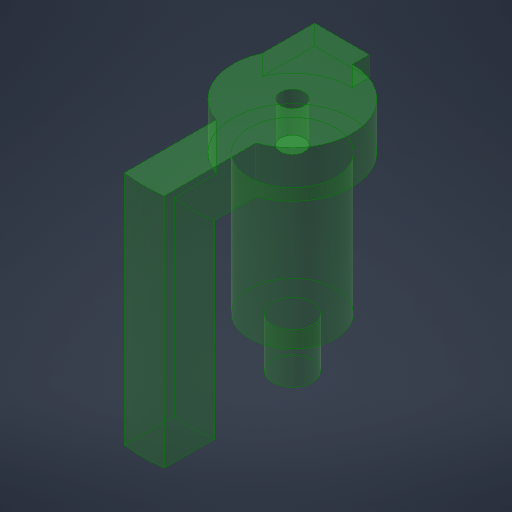
# Autodesk Inventor part: OT2-Pipette V0.4 - yoke
Saved by Autodesk Inventor 2026 (Build 300175000, 175)
## iProperties
Created: 2026-11-01
Part Number: OT2-Pipette V0.4 - yoke
Material: Generisch
Description: printed yoke on the actuator shaft (M2.5 insert), rigid pad on the plunger knob, switch tab
Document SubType Name: Modeling
Designer: benir
Density: 1 g/cm^3
Appearance: Green
Author: benir
Autodesk Inventor part; units mm, degrees
ref_plane "y=top_y - disc_h" through (0, 95, 0) normal (0, 1, 0) x (-1, 0, 0)
sketch "disc" plane through (0, 95, 0) normal (0, 1, 0) x (-1, 0, 0)
  circle A0 centre (-8.2, -3.46) radius 9
  point P0 (0, 0)
  dimension "d3" = 3.46
  dimension "d4" = 8.2
  dimension "d5" = 18
  constraints: 1 centre point
  measures "d3" vertical distance of point (0, 0) A0.centre
  measures "d4" horizontal distance of point (0, 0) A0.centre
  measures "d5" diameter of A0
extrude "Extrusion2" add sketch "disc" along normal blind 7
ref_plane "y=pad_face" through (0, 74, 0) normal (0, 1, 0) x (-1, 0, 0)
sketch "post" plane through (0, 74, 0) normal (0, 1, 0) x (-1, 0, 0)
  circle A0 centre (-8.2, -3.46) radius 6.5
  point P0 (0, 0)
  dimension "d9" = 3.46
  dimension "d10" = 8.2
  dimension "d11" = 13
  constraints: 1 centre point
  measures "d9" vertical distance of point (0, 0) A0.centre
  measures "d10" horizontal distance of point (0, 0) A0.centre
  measures "d11" diameter of A0
extrude "post with pad face" add sketch "post" along normal blind 21
ref_plane "y=top_y - tab_h" through (0, 99, 0) normal (0, 1, 0) x (-1, 0, 0)
sketch "switch tab" plane through (0, 99, 0) normal (0, 1, 0) x (-1, 0, 0)
  line L0 (0, -15) -> (-8.2, -15)
  line L1 (-8.2, -15) -> (-8.2, -3.46)
  line L2 (-8.2, -3.46) -> (0, -3.46)
  line L3 (0, -3.46) -> (0, -15)
  line L4 (0, -19.108) -> (0, 9.648) projected
  line L5 (4.4, 0) -> (-20.8, 0) projected
  point P0 (0, 0)
  dimension "d15" = 8.2
  dimension "d16" = 11.54
  dimension "d17" = 15
  constraints: 8 end point, 2 parallel, 1 collinear, 1 horizontal, 1 perpendicular
  measures "d15" distance of L0.start L0.end
  measures "d16" distance of L2.end L0.start
  measures "d17" distance of point (0, 0) L0.start
extrude "Extrusion4" add sketch "switch tab" along normal blind 3
ref_plane "y=top_y - insert_m25_depth" through (0, 96, 0) normal (0, 1, 0) x (-1, 0, 0)
sketch "M2.5 insert hole" plane through (0, 96, 0) normal (0, 1, 0) x (-1, 0, 0)
  circle A0 centre (-8.2, -3.46) radius 1.8
  point P0 (0, 0)
  dimension "d21" = 3.46
  dimension "d22" = 8.2
  dimension "d23" = 3.6
  constraints: 1 centre point
  measures "d21" vertical distance of point (0, 0) A0.centre
  measures "d22" horizontal distance of point (0, 0) A0.centre
  measures "d23" diameter of A0
extrude "Extrusion5" cut sketch "M2.5 insert hole" along normal blind 7
sketch "Skizze6" plane through (8.2, 74, -3.46) normal (0, -1, 0) x (1, 0, 0)
  circle A0 centre (0, 0) radius 1.8 projected
  circle A1 centre (0, 0) radius 3.0002
  point P0 (-8.2, 3.46)
  dimension "d26" = 6.0004
  constraints: 1 centre point, 1 coincident
  measures "d26" diameter of A1
extrude "Extrusion6" add sketch "Skizze6" along normal blind 7.5 contours A0 | A1
sketch "Skizze7" plane through (0, 102, 0) normal (0, 1, 0) x (1, 0, 0)
  arc A0 (0, 7.1694) -> (8.2, 12.46) centre (8.2, 3.46) ccw projected
  line L0 (5.2, -5.0253) -> (5.2, -21.54)
  line L1 (5.2, -21.54) -> (11.2, -21.54)
  line L2 (11.2, -21.54) -> (11.2, -5.0253)
  line L3 (-8.2835, 0) -> (25.4628, 0) projected
  point P0 (0, 0)
  point P1 (13.0793, -4.1026)
  point P2 (8.2, -21.54)
  dimension "d31" = 6
  dimension "d32" = 90
  dimension "d35" = 25
  dimension "d36" = 3
  constraints: 6 end point, 4 point on circle, 2 parallel, 1 midpoint
  measures "d31" distance of L0.end L1.end
  measures "d32" angle of L1 L2
  measures "d35" distance from line of L1 A0.centre
  measures "d36" distance from line of A0.centre L2
extrude "Extrusion7" add sketch "Skizze7" against normal up to surface (7 mm away) contours A0 L2 L1 L0
sketch "Skizze8" plane through (0, 95, 0) normal (0, -1, 0) x (1, 0, 0)
  circle A0 centre (8.2, -3.46) radius 1.8 projected
  arc A1 (11.2, 11.2369) -> (5.2, 11.2369) centre (8.2, -3.46) ccw
  circle A2 centre (8.2, -3.46) radius 6.5 projected
  arc A3 (5.2, 5.0253) -> (11.2, 5.0253) centre (8.2, -3.46) ccw projected
  line L0 (11.2, 5.0253) -> (11.2, 21.54) projected
  line L1 (11.2, 21.54) -> (5.2, 21.54) projected
  line L2 (5.2, 21.54) -> (5.2, 5.0253) projected
  arc A4 (11.2, 18.8391) -> (5.2, 18.8391) centre (8.2, -3.46) ccw
  point P0 (0, 0)
  dimension "d39" = 30
  dimension "d40" = 45
  constraints: 4 point on circle, 4 point on line, 2 centre point, 2 coincident
  measures "d39" diameter of A1
  measures "d40" diameter of A4
extrude "Extrusion8" add sketch "Skizze8" along normal up to surface (28.5 mm away) contours A1 L2 A4 L0
extrude "Extrusion9" cut sketch "Skizze8" against normal through all contours A4 L2 L1 L0
equation "\"d3\" = -pip_z"
equation "\"d4\" = pip_x"
equation "\"d5\" = yoke_d"
equation "\"d6\" = disc_h"
equation "\"d9\" = -pip_z"
equation "\"d10\" = pip_x"
equation "\"d11\" = pad_d"
equation "\"d12\" = -disc_h + top_y - pad_face"
equation "\"d15\" = pip_x - tab_x0"
equation "\"d16\" = pip_z - tab_z_in - sw_z0"
equation "\"d17\" = -tab_z_in - sw_z0"
equation "\"d18\" = tab_h"
equation "\"d21\" = -pip_z"
equation "\"d22\" = pip_x"
equation "\"d23\" = insert_m25"
equation "\"d24\" = insert_m25_depth + cut_over"
equation "\"d36\" = 0.5 * d31"
equation "\"yoke_d\" = 18"
equation "\"disc_h\" = 7"
equation "\"pad_d\" = 13"
equation "\"top_y\" = 102"
equation "\"pad_face\" = 74"
equation "\"pip_x\" = 8.2"
equation "\"tab_x0\" = 0"
equation "\"pip_z\" = -3.46"
equation "\"tab_z_in\" = 1"
equation "\"sw_z0\" = -16"
equation "\"tab_h\" = 3"
equation "\"insert_m25\" = 3.6"
equation "\"insert_m25_depth\" = 6"
equation "\"cut_over\" = 1"
body "Solid2"
